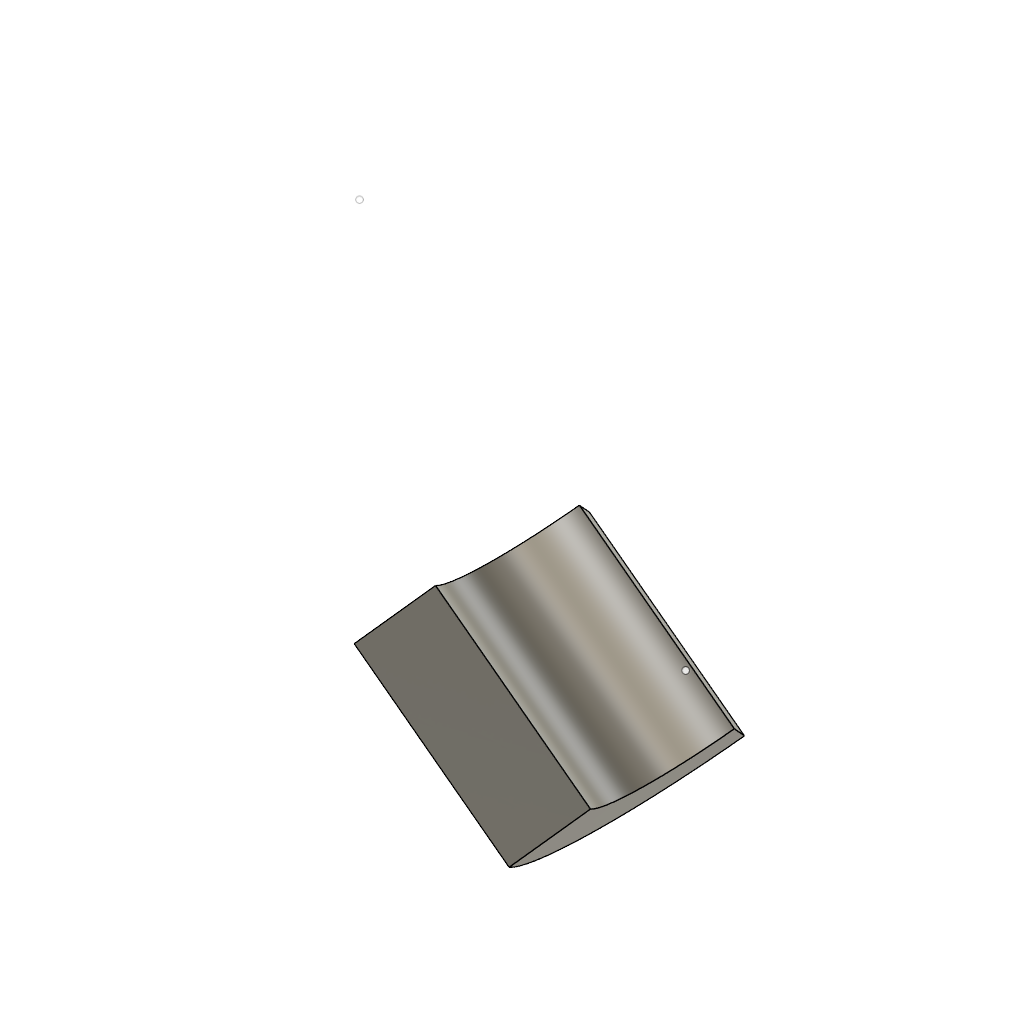
holdout_a_edit_second (Autodesk Fusion 360 design; units mm, degrees)
part number: 2026-11-27-16-03-36-866
Autodesk Fusion 360 part; units mm, degrees
sketch "AxisSupport" plane through (0, 0, 0) normal (0, 0, 1) x (1, 0, 0)
  point P0 (21, -13)
  point P1 (-11, 11)
sketch "RevolveProfile" plane through (0, 0, 0) normal (0, 0, 1) x (1, 0, 0)
  line L0 (17.6, -24.2) -> (2.4, -12.8)
  line L1 (2.4, -12.8) -> (-1.8, -18.4)
  line L2 (-1.8, -18.4) -> (13.4, -29.8)
  line L3 (13.4, -29.8) -> (17.6, -24.2)
revolve "UnequalRevolve" add sketch "RevolveProfile" angle 47 about axis through (27.4, -17.8, 0) along (-0.8, 0.6, 0) second angle 38
